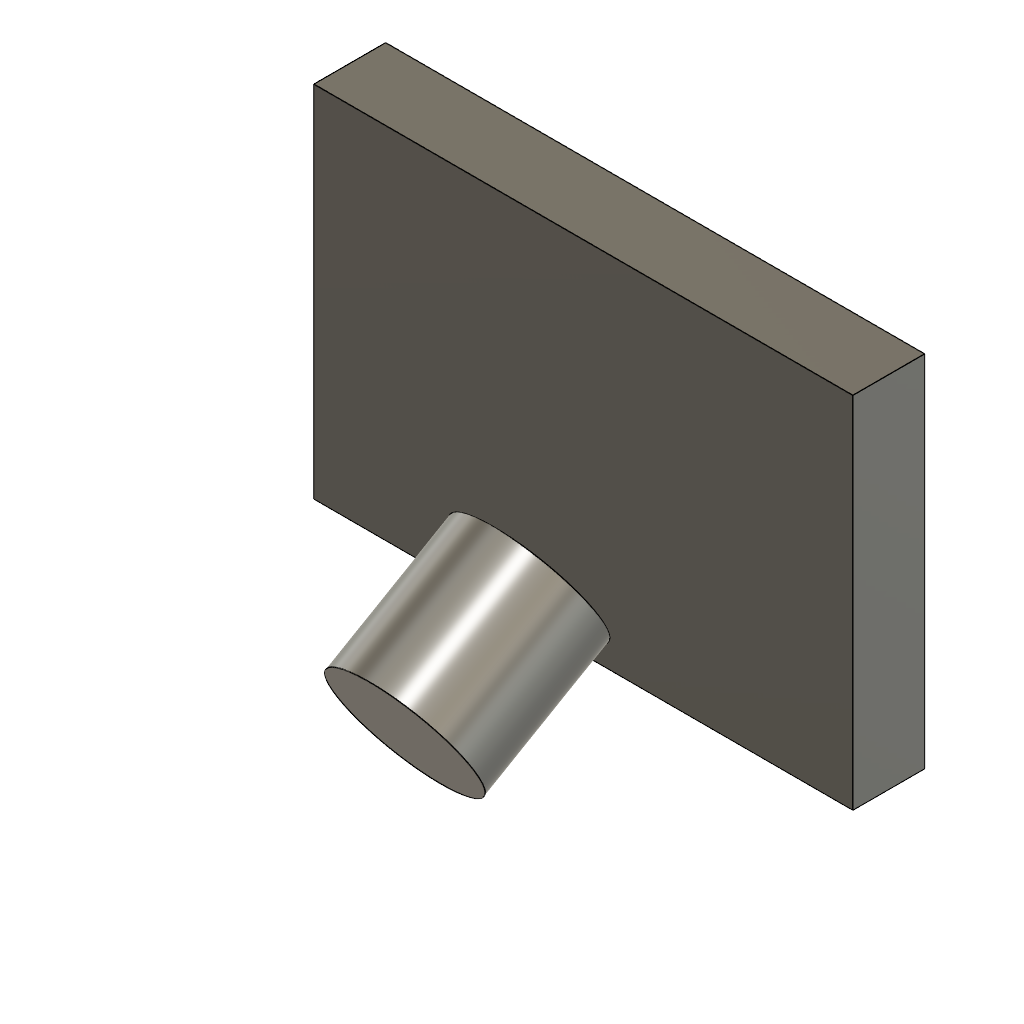
sk_on_angled_plane (Autodesk Fusion 360 design; units mm, degrees)
part number: 2026-11-13-14-35-47-138
Autodesk Fusion 360 part; units mm, degrees
sketch "Sketch1" plane through (0, 0, 0) normal (0, 0, 1) x (1, 0, 0)
  line L0 (0, 0) -> (30, 0)
  line L1 (30, 0) -> (30, 20)
  line L2 (30, 20) -> (0, 20)
  line L3 (0, 20) -> (0, 0)
extrude "Extrude1" add sketch "Sketch1" along normal blind 4 makes body 1
ref_plane "WorkPlane1" through (15, 0, 4) normal (0, -0.5, 0.866025) x (1, 0, 0)
sketch "Sketch2" plane through (0, -1.7321, 3) normal (0, -0.5, 0.866025) x (1, 0, 0)
  circle A0 centre (15, 8) radius 4
extrude "Extrude2" add sketch "Sketch2" along normal blind 8 separate body makes body 2
